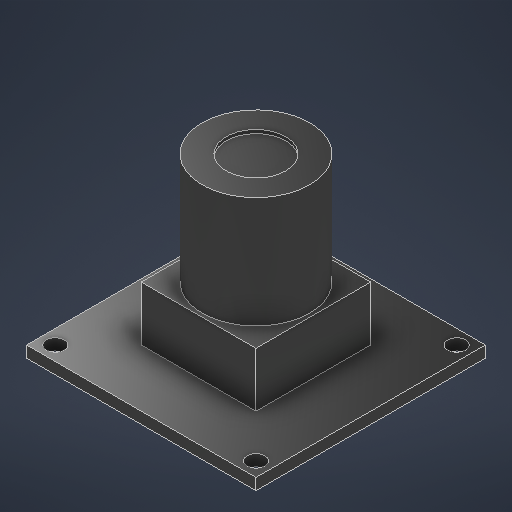
# Autodesk Inventor part: Камера
Saved by Autodesk Inventor 2026 (Build 300175050, 175E)
## iProperties
Created: 2026-10-25
Part Number: Камера
Material: Пластик АБС
Document SubType Name: Modeling
Designer: VK7
Density: 1.06 g/cm^3
Appearance: Глянцевая — черная
Author: VK7
Autodesk Inventor part; units mm, degrees
ref_plane "YZ Plane" through (0, 0, 0) normal (1, 0, 0) x (0, 1, 0)
ref_plane "XZ Plane" through (0, 0, 0) normal (0, 1, 0) x (-1, 0, 0)
ref_plane "XY Plane" through (0, 0, 0) normal (0, 0, 1) x (1, 0, 0)
sketch "Эскиз1" plane through (0, 0, 0) normal (0, 1, 0) x (-1, 0, 0)
  line L0 (0, 0) -> (32, 0)
  line L1 (32, 0) -> (32, -32)
  line L2 (32, -32) -> (0, -32)
  line L3 (0, -32) -> (0, 0)
  line L4 (0, 0) -> (0, -2)
  line L5 (0, -2) -> (2, -2)
  circle A0 centre (2, -2) radius 1.25
  line L6 (16, 0) -> (16, -32)
  line L7 (16, -16) -> (0, -16)
  circle A1 centre (2, -30) radius 1.25
  circle A2 centre (30, -30) radius 1.25
  circle A3 centre (30, -2) radius 1.25
  dimension "d0" = 32
  dimension "d1" = 32
  dimension "d2" = 2
  dimension "d3" = 2
  dimension "d4" = 2.5
  dimension "d7" = 360
  constraints: 16 end point, 4 centre point, 4 midpoint, 2 parallel, 2 perpendicular, 1 coincident, 1 horizontal, 1 point on line, 9 other
  measures "d0" distance of L1.end L2.end
  measures "d1" distance of L0.end L1.end
  measures "d2" distance of L0.start L4.end
  measures "d3" distance of L4.end L5.end
  measures "d4" diameter of A0
extrude "Выдавливание1" add sketch "Эскиз1" along normal blind 1.6
sketch "Эскиз2" plane through (0, 1.6, 0) normal (0, 1, 0) x (1, 0, 0)
  line L0 (-32, 32) -> (-32, 0) projected
  line L1 (-32, 16) -> (0, 16)
  line L2 (0, 0) -> (0, 32) projected
  line L3 (-24, 8) -> (-8, 8)
  line L4 (-8, 8) -> (-8, 24)
  line L5 (-8, 24) -> (-24, 24)
  line L6 (-24, 24) -> (-24, 8)
  line L7 (-24, 8) -> (-8, 24) construction
  line L8 (-8, 8) -> (-24, 24) construction
  point P0 (-16, 16)
  dimension "d11" = 16
  dimension "d12" = 16
  constraints: 14 end point, 5 midpoint, 2 parallel, 1 horizontal, 1 perpendicular
  measures "d11" distance of L5.end L4.end
  measures "d12" distance of L4.end L3.end
extrude "Выдавливание2" add sketch "Эскиз2" along normal blind 7.6
sketch "Эскиз3" plane through (0, 9.2, 0) normal (0, 1, 0) x (1, 0, 0)
  line L0 (-8, 8) -> (-8, 24) projected
  line L1 (-8, 16) -> (-24, 16)
  line L2 (-24, 24) -> (-24, 8) projected
  circle A0 centre (-16, 16) radius 7.5
  point P0 (0, 0)
  dimension "d15" = 15
  constraints: 3 midpoint, 2 end point, 1 centre point
  measures "d15" diameter of A0
extrude "Выдавливание3" add sketch "Эскиз3" along normal blind 15.5
sketch "Эскиз4" plane through (-16, 24.7, -16) normal (0, 1, 0) x (1, 0, 0)
  circle A0 centre (0, 0) radius 4.15
  point P0 (16, -16)
  dimension "d18" = 8.3
  constraints: 1 centre point
  measures "d18" diameter of A0
extrude "Выдавливание4" cut sketch "Эскиз4" against normal blind 0.5
